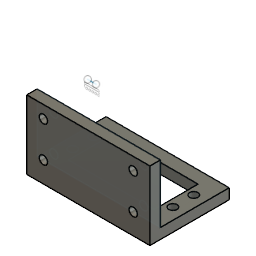
servo holder finallllllllll (Autodesk Fusion 360 design; units mm, degrees)
part number: 2026-04-19-13-53-33-612
Autodesk Fusion 360 part; units mm, degrees
sketch "Sketch1" plane through (0, 0, 0) normal (0, 1, 0) x (1, 0, 0)
  line L0 (32.7947, 39.5117) -> (91.7947, 39.5117)
  line L1 (91.7947, 39.5117) -> (91.7947, 6.5117)
  line L2 (91.7947, 6.5117) -> (32.7947, 6.5117)
  line L3 (32.7947, 6.5117) -> (32.7947, 39.5117)
  line L4 (62.2947, 33.5117) -> (41.7947, 33.5117)
  line L5 (62.2947, 33.5117) -> (82.7947, 33.5117)
  line L6 (62.2947, 33.5117) -> (82.7947, 33.5117)
  line L7 (62.2947, 12.5117) -> (41.7947, 12.5117)
  line L8 (62.2947, 12.5117) -> (82.7947, 12.5117)
  line L9 (41.7947, 23.0117) -> (41.7947, 33.5117)
  line L10 (41.7947, 23.0117) -> (41.7947, 12.5117)
  line L11 (82.7947, 23.0117) -> (82.7947, 33.5117)
  line L12 (82.7947, 23.0117) -> (82.7947, 12.5117)
  circle A0 centre (38.2947, 18.0117) radius 2
  circle A1 centre (38.2947, 28.0117) radius 2
  circle A2 centre (86.2947, 28.0117) radius 2
  circle A3 centre (86.2947, 18.0117) radius 2
  dimension "d1" = 59
  dimension "d2" = 33
  dimension "d9" = 4
  dimension "d10" = 10
  dimension "d11" = 4
  dimension "d12" = 48
  dimension "d13" = 10
  dimension "d14" = 4
  dimension "d15" = 4
  constraint horizontal L0
  constraint vertical L1
  constraint horizontal L2
  constraint vertical L3
  constraint perpendicular L3 L4
  constraint perpendicular L1 L5
  constraint perpendicular L3 L7
  constraint perpendicular L1 L8
  constraint perpendicular L4 L9
  constraint perpendicular L7 L10
  constraint perpendicular L6 L11
  constraint perpendicular L8 L12
  measures "d1" distance of L0.start L0.end
  measures "d2" distance of L0.start L2.end
  measures "d9" diameter of A0
  measures "d10" distance of A0.centre A1.centre
  measures "d11" diameter of A1
  measures "d12" distance of A1.centre A2.centre
  measures "d13" distance of A2.centre A3.centre
  measures "d14" diameter of A2
  measures "d15" diameter of A3
sketch "Sketch2" plane through (0, 0, 0) normal (0, 1, 0) x (1, 0, 0)
sketch "Sketch3" plane through (0, 0, 0) normal (0, 1, 0) x (1, 0, 0)
sketch "Sketch4" plane through (0, 0, 0) normal (0, 1, 0) x (1, 0, 0)
sketch "Sketch5" plane through (0, 0, 0) normal (0, 1, 0) x (1, 0, 0)
extrude "Extrude1" add sketch "Sketch1" along normal blind 5
sketch "Sketch6" plane through (0, 0, 0) normal (0, 0, 1) x (1, 0, 0)
sketch "Sketch7" plane through (0, 0, -6.5117) normal (0, 0, 1) x (1, 0, 0)
  line L0 (32.7947, 0) -> (91.7947, 0)
  line L1 (91.7947, 0) -> (91.7947, 5)
  line L2 (32.7947, 5) -> (32.7947, 0)
  line L3 (32.7947, 0) -> (32.7947, 33)
  line L4 (91.7947, 0) -> (91.7947, 33)
  line L5 (32.7947, 33) -> (91.7947, 33)
  line L6 (32.7947, 0) -> (91.7947, 0)
  line L7 (62.2947, 33) -> (32.7947, 33)
  line L8 (83.7947, 29) -> (83.7947, 27)
  circle A0 centre (40.7947, 27) radius 2
  circle A1 centre (83.7947, 27) radius 2
  circle A2 centre (40.7947, 10) radius 2
  circle A3 centre (83.7947, 10) radius 2
  dimension "d18" = 33
  dimension "d19" = 33
  dimension "d28" = 4
  dimension "d29" = 4
  dimension "d33" = 4
  dimension "d35" = 4
  constraint coincident L0.start L2.end
  constraint perpendicular L0 L3
  constraint coincident L0.end L1.start
  constraint midpoint L5 L7.start
  constraint perpendicular L3 L7
  constraint perpendicular L5 L8
  constraint coincident L8.end A1.centre
  constraint coincident A1 L8.start
  measures "d18" distance of L0.start L3.end
  measures "d19" distance of L0.end L4.end
  measures "d28" diameter of A0
  measures "d29" diameter of A1
  measures "d33" diameter of A2
  measures "d35" diameter of A3
sketch "Sketch8" plane through (0, 5, 0) normal (0, 1, 0) x (-1, 0, 0)
  line L0 (-41.7947, -33.5117) -> (-82.7947, -33.5117)
  line L1 (-82.7947, -33.5117) -> (-82.7947, -12.5117)
  line L2 (-82.7947, -12.5117) -> (-41.7947, -12.5117)
  line L3 (-41.7947, -12.5117) -> (-41.7947, -33.5117)
  circle A0 centre (-38.2947, -28.0117) radius 2
  circle A1 centre (-38.2947, -18.0117) radius 2
  circle A2 centre (-86.2947, -28.0117) radius 2
  circle A3 centre (-86.2947, -18.0117) radius 2
  line L4 (-32.7947, -6.5117) -> (-91.7947, -6.5117)
  line L5 (-91.7947, -6.5117) -> (-91.7947, -39.5117)
  line L6 (-91.7947, -39.5117) -> (-32.7947, -39.5117)
  line L7 (-32.7947, -39.5117) -> (-32.7947, -6.5117)
sketch "Sketch9" plane through (0, 0, -6.5117) normal (0, 0, 1) x (1, 0, 0)
  line L0 (33, 5) -> (92, 5)
  constraint horizontal L0
extrude "Extrude2" add sketch "Sketch7" along normal blind 5
sketch "Sketch10" plane through (0, 0, -6.5117) normal (0, 0, -1) x (-1, 0, 0)
  line L0 (-91.7947, 5) -> (-32.7947, 5)
  line L1 (-32.7947, 5) -> (-32.7947, 33)
  line L2 (-32.7947, 33) -> (-91.7947, 33)
  line L3 (-91.7947, 33) -> (-91.7947, 5)
  circle A0 centre (-83.7947, 27) radius 2
  circle A1 centre (-40.7947, 10) radius 2
  circle A2 centre (-40.7947, 27) radius 2
  circle A3 centre (-83.7947, 10) radius 2
  line L4 (-61, 49) -> (-57, 49)
  constraint horizontal L4
extrude "Extrude3" [rolled back] along distance 2 taper angle 0
sketch "Sketch11" plane through (0, 0, 0) normal (0, 0, 1) x (1, 0, 0)
